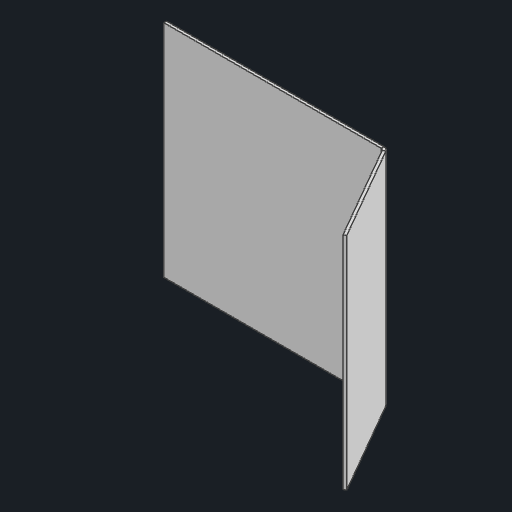
# Autodesk Inventor part: flange-angle
Saved by Autodesk Inventor 2026.1 (Build 301233000, 233)
## iProperties
Created: 2026-10-30
Part Number: flange-angle
Material: Generic
Document SubType Name: Sheet Metal
Designer: anony
Density: 1 g/cm^3
Sheet Metal Rule: Default_mm
Appearance: Default
Author: anony
Autodesk Inventor part; units mm, degrees
ref_plane "YZ Plane" through (0, 0, 0) normal (1, 0, 0) x (0, 1, 0)
ref_plane "XZ Plane" through (0, 0, 0) normal (0, 1, 0) x (-1, 0, 0)
ref_plane "XY Plane" through (0, 0, 0) normal (0, 0, 1) x (1, 0, 0)
sketch "Sketch1" plane through (0, 0, 0) normal (0, 0, 1) x (1, 0, 0)
  line L0 (-20, -20) -> (20, -20)
  line L1 (20, -20) -> (20, 20)
  line L2 (20, 20) -> (-20, 20)
  line L3 (-20, 20) -> (-20, -20)
extrude "Plate1" add sketch "Sketch1" along normal blind 0.5
sketch "Sketch2" plane through (19.567, 20, 0.25) normal (0.8660254, 0, -0.5) x (0, 1, 0)
  line L0 (-40, 0) -> (0, 0)
  line L1 (0, 0) -> (0, 20)
  line L2 (0, 20) -> (-40, 20)
  line L3 (-40, 20) -> (-40, 0)
  constraints: 6 end point, 1 horizontal, 1 perpendicular, 1 vertical
edge flange "Flange1" height 20 angle 60 thickness 0.5 bend radius 0.5 thickness toward (0.8660254, 0, -0.5) relief tear relief width 0.5 relief depth 0.25 edges at (20, 0, 0.5) wall of the first edge with corners at (19.567, -20, 0.25) (19.567, 20, 0.25) (29.567, 20, 17.5705) (29.567, -20, 17.5705)
bend "Bend1"
corner "Corner1"
equation "\"d0\" = Thickness"
equation "\"d1\" = Thickness"
equation "\"d2\" = 0.5 * Thickness"
equation "\"d3\" = 2 * Thickness"
equation "\"d4\" = Thickness"
equation "\"d7\" = Thickness"
equation "\"d8\" = 4 * Thickness"
equation "\"d10\" = JacobiRadiusSize"
equation "\"BendRadius\" = Thickness"
equation "\"BendReliefWidth\" = Thickness"
equation "\"BendReliefDepth\" = 0.5 * Thickness"
equation "\"CornerReliefSize\" = 4 * Thickness"
equation "\"MinimumRemnant\" = 2 * Thickness"
equation "\"TransitionRadius\" = BendRadius"
equation "\"JacobiRadiusSize\" = BendRadius"
equation "\"GapSize\" = Thickness"
equation "\"Thickness\" = 0.5"
body "Solid1"
